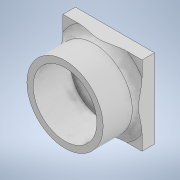
# Autodesk Inventor part: sharp_rotire_top
Saved by Autodesk Inventor 2020 (Build 240168000, 168)
## iProperties
Created: 2023-10-29
Part Number: sharp_rotire_top
Material: Generic
Document SubType Name: Modeling
Designer: user
Density: 1 g/cm^3
Appearance: Default
Author: user
Autodesk Inventor part; units mm, degrees
ref_plane "YZ Plane" through (0, 0, 0) normal (1, 0, 0) x (0, 1, 0)
ref_plane "XZ Plane" through (0, 0, 0) normal (0, 1, 0) x (-1, 0, 0)
ref_plane "XY Plane" through (0, 0, 0) normal (0, 0, 1) x (1, 0, 0)
sketch "Sketch1" plane through (0, 0, 0) normal (0, 0, 1) x (1, 0, 0)
  line L0 (-13.8909, 7.6454) -> (5.1091, 7.6454)
  line L1 (5.1091, 7.6454) -> (5.1091, -11.3546)
  line L2 (5.1091, -11.3546) -> (-13.8909, -11.3546)
  line L3 (-13.8909, -11.3546) -> (-13.8909, 7.6454)
  point P0 (0, 0)
  dimension "d0" = 19
  dimension "d1" = 19
  constraints: 8 end point, 2 parallel, 1 horizontal, 1 perpendicular
  measures "d0" distance of L1.end L2.end
  measures "d1" distance of L0.end L1.end
extrude "Extrusion1" add sketch "Sketch1" along normal blind 3
sketch "Sketch2" plane through (0, 0, 3) normal (0, 0, 1) x (1, 0, 0)
  line L0 (5.1091, -11.3546) -> (5.1091, 7.6454) projected
  line L1 (5.1091, -1.8546) -> (-13.8909, -1.8546)
  line L2 (-13.8909, 7.6454) -> (-13.8909, -11.3546) projected
  line L3 (5.1091, 7.6454) -> (-13.8909, 7.6454) projected
  line L4 (-4.3909, 7.6454) -> (-4.3909, -11.3546)
  line L5 (5.1091, -11.3546) -> (5.1091, 7.6454) projected
  line L6 (5.1091, 7.6454) -> (-13.8909, 7.6454) projected
  line L7 (-13.8909, 7.6454) -> (-13.8909, -11.3546) projected
  line L8 (-13.8909, -11.3546) -> (5.1091, -11.3546) projected
  circle A0 centre (-4.3909, -1.8546) radius 7.65
  circle A1 centre (-4.3909, -1.8546) radius 9.15
  point P0 (0, 0)
  dimension "d4" = 15.3
  dimension "d5" = 18.3
  constraints: 5 midpoint, 4 end point, 2 centre point, 1 coincident, 1 vertical
  measures "d4" diameter of A0
  measures "d5" diameter of A1
extrude "Extrusion2" add sketch "Sketch2" along normal blind 9 contours A1 L4 A0 L1 | L1 A0 L4 A1 | A1 L1 A0 L4 | L4 A0 L1 A1
fillet "Fillet1" radius 2 1 edges at (-13.5409, -1.8546, 3)
body "Solid1"
